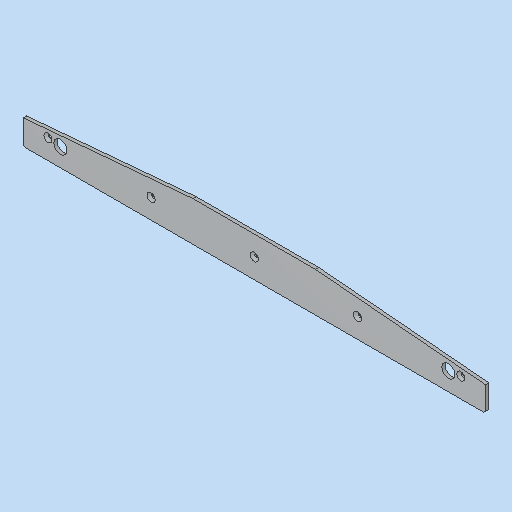
# Autodesk Inventor part: MM0948AN120_G01_111
Saved by Autodesk Inventor 2023.3 (Build 273359000, 359)
## iProperties
RuleStatus: InUse
Created: 2023-03-23
Part Number: MM0948AN120_G01_111
Material: 3.3535 AlMg3 - AW 5754 (Blech)
Description: =<RBPARTNOTITLE2>
Document SubType Name: Modeling
Designer: ric7an
Mass: 243.957 g
Surface Area: 507.192 cm^2
Volume: 90.3879 cm^3
Density: 2.699 g/cm^3
Appearance: Aluminium AnP
AnP_Kategorie: 1
AnP_Material: =<Material>
MaxAbmaße: 4 x 48 x 560 (FM)
AnP_TemplVers: 20200821
RBDOCUMENTTYPE: DRF
RBDOCUMENTVERSION: 00
RBDRAWINGMAINSCALE: 1:1
RBDRAWINGMISSINGSPEC: --
RBDRAWINGVOLUME: --
RBDSV1: 0850
RBGBEDGESIN1: +0,5
RBGBEDGESIN2: +0,2
RBGBEDGESOUT1: -0,3
RBGBEDGESOUT2: -0,1
RBMATERIAL: =<Material>
RBMATMEETS: --
RBMATNO: =<Part Number>
RBPARTMADEOF: 4 x 48 x 560 (FM)
RBPARTNO: SIEHE MNR
RBPARTNOTITLE1: manufactured part
RBPARTNOTITLE2: Anfertigungsteil
RBPARTSAFETYINDICATOR: --
RBSURFACE: anodised colourless
RBSURFACE2: eloxiert farblos
RBZEDGESNORM: ISO13715:2002-06
RBZGENDIMCLASS: m
RBZGENDIMNORM: ISO 2768-1:1989-11
RBZGENGEOCLASS: H
RBZGENGEONORM: ISO 2768-2:1989-11
RBZSURFACENORM: ISO13D2:2002-02
RBZTOLERANCENORM: ISO 14405-1:2010-12
AnP_Kommentar_aktuell: =<Comments>
AnP_Material_aktuell: =<Material>
Author: FH/Wi
Keywords: =<RBPARTMADEOF>
Comments: =<RBSURFACE2>
Revision Number: 01
Autodesk Inventor part; units mm, degrees
ref_plane "YZ Plane" through (0, 0, 0) normal (1, 0, 0) x (0, 1, 0)
ref_plane "XZ Plane" through (0, 0, 0) normal (0, 1, 0) x (-1, 0, 0)
ref_plane "XY Plane" through (0, 0, 0) normal (0, 0, 1) x (1, 0, 0)
sketch "Skizze1" plane through (0, 0, 0) normal (0, 0, 1) x (1, 0, 0)
  line L0 (-280, 48) -> (280, 48)
  line L1 (280, 48) -> (280, 0)
  line L2 (280, 0) -> (-280, 0)
  line L3 (-280, 0) -> (-280, 48)
  line L4 (0, 57.6) -> (0, -9.6) projected
  line L5 (-392, 0) -> (392, 0) projected
  point P0 (0, 0)
  dimension "d0" = 560
  dimension "d1" = 48
  constraints: 8 end point, 2 parallel, 1 collinear, 1 horizontal, 1 perpendicular, 1 other
  measures "d0" distance of L1.end L2.end
  measures "d1" distance of L0.end L1.end
extrude "Extrusion1" add sketch "Skizze1" along normal blind 4
sketch "Skizze2" plane through (0, 0, 4) normal (0, 0, 1) x (1, 0, 0)
  line L0 (0, 57.6) -> (0, -9.6) projected
  line L1 (280, 48) -> (-280, 48) projected
  line L2 (-250, 24) -> (0, 24)
  line L3 (0, 24) -> (250, 24)
  point P0 (0, 0)
  point P1 (-125, 24)
  point P2 (125, 24)
  point P3 (125, 24)
  point P4 (-125, 24)
  dimension "d4" = 500
  dimension "d5" = 24
  constraints: 4 end point, 3 midpoint, 2 coincident, 2 horizontal, 1 horizontal alignment, 1 symmetric about line
  measures "d4" distance of L3.end L2.start
  measures "d5" distance from line of L1 L3.end
hole "Bohrung1" at (-250, 24, 4) at (250, 24, 4) at (0, 24, 4) at (-125, 24, 4) at (125, 24, 4) direction (0, 0, -1) diameter 4.5 end through all countersink diameter 10 countersink angle 90 clearance for "Innensechskant-Senkkopfschraube ISO 10642" size "M4" standard "ISO"
chamfer "Fase1" distance 2 angle 45 2 edges at (280, 0, 2) (-280, 0, 2)
chamfer "Fase2" distance 18 angle 85 1 edges at (280, 48, 2) measured on face at (280, 17.3333, 1.3333)
chamfer "Fase3" distance 18 angle 85 1 edges at (-280, 48, 2) measured on face at (-280, 32.6667, 1.3333)
sketch "Skizze4" plane through (0, 0, 4) normal (0, 0, 1) x (1, 0, 0)
  line L0 (-280, 30) -> (-280, 2) projected
  line L1 (-278, 0) -> (278, 0) projected
  line L2 (280, 2) -> (280, 30) projected
  point P0 (0, 0)
  point P1 (-235, 22)
  point P2 (235, 22)
  dimension "d32" = 45
  dimension "d33" = 22
  dimension "d41" = 45
  constraints: 1 horizontal alignment
  measures "d32" distance from line of point (-235, 22) L0
  measures "d33" distance from line of L1 point (-235, 22)
  measures "d41" distance from line of L2 point (235, 22)
hole "Bohrung3" at (-235, 22, 4) at (235, 22, 4) direction (0, 0, -1) diameter 16 end through all
equation "\"d41\" = d32"
